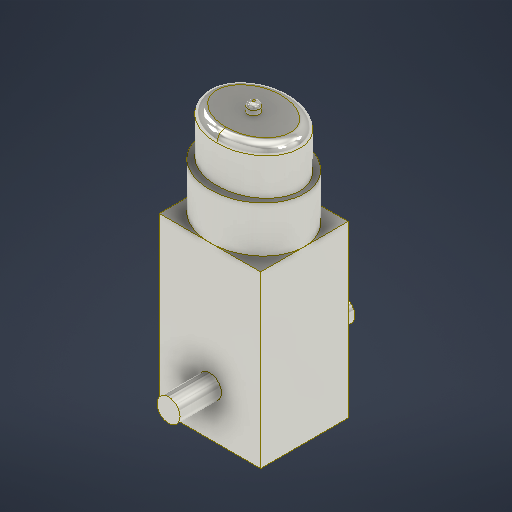
# Autodesk Inventor part: MOTOR_B
Saved by Autodesk Inventor 2026.2 (Build 302298010, 298A)
## iProperties
Created: 2026-10-27
Part Number: MOTOR_B
Material: Plata
Document SubType Name: Modeling
Designer: efrey
Density: 10.49 g/cm^3
Appearance: Plata
Author: efrey
Autodesk Inventor part; units mm, degrees
ref_plane "YZ Plane" through (0, 0, 0) normal (1, 0, 0) x (0, 1, 0)
ref_plane "XZ Plane" through (0, 0, 0) normal (0, 1, 0) x (-1, 0, 0)
ref_plane "XY Plane" through (0, 0, 0) normal (0, 0, 1) x (1, 0, 0)
sketch "Boceto1" plane through (0, 0, 0) normal (0, 0, 1) x (1, 0, 0)
  line L0 (0, 0) -> (22, 0)
  line L1 (22, 0) -> (22, 37)
  line L2 (22, 37) -> (0, 37)
  line L3 (0, 37) -> (0, 0)
  dimension "d0" = 22
  dimension "d1" = 37
  constraints: 8 end point, 2 parallel, 1 horizontal, 1 perpendicular
  measures "d0" distance of L2.end L1.end
  measures "d1" distance of L1.end L0.end
extrude "Extrusión1" add sketch "Boceto1" along normal mid plane 19
sketch "Boceto2" plane through (0, 0, 9.5) normal (0, 0, 1) x (1, 0, 0)
  circle A0 centre (11, 10) radius 2.5
  line L0 (0, 0) -> (22, 0) projected
  line L1 (22, 0) -> (22, 37) projected
  point P0 (11, 0)
  dimension "d4" = 5
  dimension "d5" = 10
  dimension "d6" = 11
  constraints: 1 centre point, 1 midpoint
  measures "d4" diameter of A0
  measures "d5" distance of point (11, 0) A0.centre
  measures "d6" distance from line of L1 A0.centre
extrude "Extrusión2" add sketch "Boceto2" along normal blind 9
sketch "Boceto3" plane through (0, 37, 9.5) normal (0, 1, 0) x (1, 0, 0)
  ellipse E0 centre (11, 9.5) end of major axis (22, 9.5) minor radius 9.5
  line L0 (0, 19) -> (0, 0) projected
  line L1 (0, 19) -> (22, 19) projected
  line L2 (22, 0) -> (0, 0) projected
  line L3 (22, 19) -> (22, 0) projected
  point P0 (0, 9.5)
  constraints: 1 centre point, 5 other
extrude "Extrusión3" add sketch "Boceto3" along normal blind 10 contours E0
sketch "Boceto4" plane through (0, 47, 9.5) normal (0, 1, 0) x (1, 0, 0)
  ellipse E0 centre (11, 9.5) end of major axis (22, 9.5) minor radius 9.5 (11, 0) -> (22, 9.5) ccw projected
  ellipse E1 centre (11, 9.5) end of major axis (11, 1.5) minor radius 10
  ellipse E2 centre (11, 9.5) end of major axis (22, 9.5) minor radius 9.5 projected
  point P0 (0, 9.5)
  dimension "d12" = 8
  dimension "d13" = 10
  constraints: 1 coincident, 4 other
extrude "Extrusión4" add sketch "Boceto4" along normal blind 10 contours E1
fillet "Empalme1" radius 2 1 edges at (1, 57, 0)
sketch "Boceto5" plane through (0, 0, -9.5) normal (0, 0, -1) x (-1, 0, 0)
  circle A0 centre (-11, 10) radius 2.5 projected
  circle A1 centre (-11, 10) radius 2.5
  point P0 (0, 0)
  constraints: 1 centre point, 1 coincident
extrude "Extrusión5" add sketch "Boceto5" along normal blind 10
sketch "Boceto6" plane through (0, 57, 9.5) normal (0, 1, 0) x (1, 0, 0)
  ellipse E0 centre (11, 9.5) end of major axis (21, 9.5) minor radius 8 projected
  circle A0 centre (11, 9.5) radius 1.25
  point P0 (0, 9.5)
  dimension "d19" = 2.5
  constraints: 1 centre point, 1 coincident
  measures "d19" diameter of A0
extrude "Extrusión6" add sketch "Boceto6" along normal blind 2 contours A0
fillet "Empalme2" radius 1 1 edges at (9.75, 59, 0)
